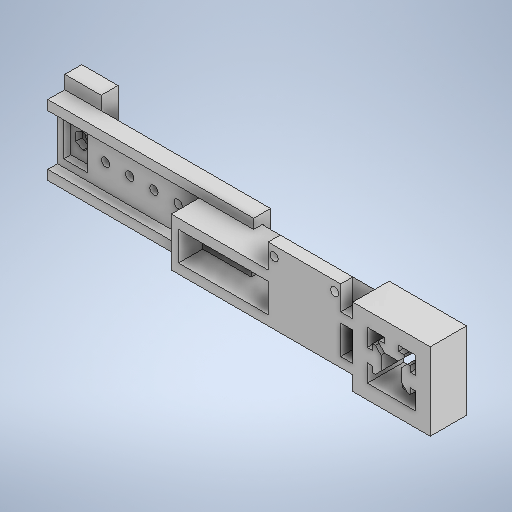
# Autodesk Inventor part: Sujetador_Camara_Modular
Saved by Autodesk Inventor 2025.3 (Build 293356030, 356C)
## iProperties
Created: 2026-06-30
Part Number: Sujetador_Camara_Modular
Material: Generic
Document SubType Name: Modeling
Designer: pablo
Density: 1 g/cm^3
Appearance: Default
Author: pablo
Autodesk Inventor part; units mm, degrees
ref_plane "YZ Plane" through (0, 0, 0) normal (1, 0, 0) x (0, 1, 0)
ref_plane "XZ Plane" through (0, 0, 0) normal (0, 1, 0) x (-1, 0, 0)
ref_plane "XY Plane" through (0, 0, 0) normal (0, 0, 1) x (1, 0, 0)
sketch "Sketch1" plane through (0, 0, 0) normal (0, 0, 1) x (1, 0, 0)
  line L0 (-2.8, -10) -> (-2.8, -7.8)
  line L1 (-2.8, -7.8) -> (-5.2, -7.8)
  line L2 (-5.2, -6.7) -> (-2.8, -4.3)
  line L3 (-7.8, -5.2) -> (-6.7, -5.2)
  line L4 (-6.7, -5.2) -> (-4.3, -2.8)
  line L5 (-2.8, -10) -> (-10, -10)
  line L6 (-7.8, -2.8) -> (-7.8, -5.2)
  line L7 (-7.8, -2.8) -> (-10, -2.8)
  line L8 (-10, -10) -> (-10, -2.8)
  line L9 (-5.2, -7.8) -> (-5.2, -6.7)
  line L10 (-4.3, -2.8) -> (-4.3, 0)
  line L11 (-4.3, 2.8) -> (-4.3, 0)
  line L12 (2.8, -10) -> (2.8, -7.8)
  line L13 (-10, -10) -> (10, -10)
  line L14 (2.8, -4.3) -> (0, -4.3)
  line L15 (5.2, -6.7) -> (2.8, -4.3)
  line L16 (6.7, -5.2) -> (4.3, -2.8)
  line L17 (2.8, -7.8) -> (5.2, -7.8)
  line L18 (2.8, -10) -> (10, -10)
  line L19 (5.2, -7.8) -> (5.2, -6.7)
  line L20 (-5.2, 6.7) -> (-2.8, 4.3)
  line L21 (-2.8, -4.3) -> (0, -4.3)
  line L22 (10, 10) -> (-10, 10)
  line L23 (2.8, 10) -> (10, 10)
  line L24 (-2.8, 7.8) -> (-5.2, 7.8)
  line L25 (-2.8, 10) -> (-2.8, 7.8)
  line L26 (2.8, 10) -> (2.8, 7.8)
  line L27 (2.8, 7.8) -> (5.2, 7.8)
  line L28 (-5.2, 7.8) -> (-5.2, 6.7)
  line L29 (5.2, 7.8) -> (5.2, 6.7)
  line L30 (-7.8, 5.2) -> (-6.7, 5.2)
  line L31 (-2.8, 4.3) -> (0, 4.3)
  line L32 (-6.7, 5.2) -> (-4.3, 2.8)
  line L33 (-7.8, 2.8) -> (-10, 2.8)
  line L34 (-7.8, 2.8) -> (-7.8, 5.2)
  line L35 (4.3, 2.8) -> (4.3, 0)
  line L36 (-10, 0) -> (10, 0) construction
  line L37 (10, -10) -> (10, 10)
  line L38 (-2.8, 10) -> (-10, 10)
  line L39 (0, -10) -> (0, 10) construction
  line L40 (-10, 10) -> (-10, 2.8)
  line L41 (7.8, 5.2) -> (6.7, 5.2)
  line L42 (2.8, 4.3) -> (0, 4.3)
  line L43 (5.2, 6.7) -> (2.8, 4.3)
  line L44 (7.8, 2.8) -> (10, 2.8)
  line L45 (6.7, 5.2) -> (4.3, 2.8)
  line L46 (7.8, 2.8) -> (7.8, 5.2)
  line L47 (10, 10) -> (10, 2.8)
  line L48 (7.8, -2.8) -> (10, -2.8)
  line L49 (7.8, -5.2) -> (6.7, -5.2)
  line L50 (7.8, -2.8) -> (7.8, -5.2)
  line L51 (10, 10) -> (10, -10) construction
  line L52 (10, -10) -> (10, -2.8)
  line L53 (4.3, -2.8) -> (4.3, 0)
  line L54 (-10, 10) -> (-10, -10)
  line L55 (16, 16) -> (-16, 16)
  line L56 (-16, 16) -> (-16, -16)
  line L57 (-16, -16) -> (16, -16)
  line L58 (16, -16) -> (16, 16)
  line L59 (16, 16) -> (-16, -16) construction
  line L60 (-16, 16) -> (16, -16) construction
  line L61 (-10, 10) -> (-16, 10)
  line L62 (-10, -10) -> (-16, -10)
  line L63 (-4.5, -16) -> (-12.5, -16)
  point P0 (0, 0)
  point P1 (0, 0)
  point P2 (0, 0)
  point P3 (-8.5, -16)
  point P4 (0, 0)
  point P5 (10, -2.8)
  dimension "d0" = 20
  dimension "d1" = 20
  dimension "d2" = 7.2
  dimension "d3" = 7.2
  dimension "d4" = 2.2
  dimension "d5" = 2.2
  dimension "d6" = 2.8
  dimension "d7" = 5.2
  dimension "d8" = 5.2
  dimension "d9" = 2.8
  dimension "d10" = 1.1
  dimension "d11" = 1.1
  dimension "d12" = 5.7
  dimension "d13" = 5.7
  dimension "d14" = 2.8
  dimension "d15" = 2.8
  dimension "d16" = 45
  dimension "d17" = 32
  dimension "d18" = 32
  constraints: 128 end point, 32 symmetric about line, 9 midpoint, 9 perpendicular, 7 point on line, 5 horizontal, 5 parallel, 2 coincident, 2 vertical, 1 horizontal alignment
  measures "d0" distance of L54.start L51.start
  measures "d1" distance of L51.start L13.end
  measures "d2" distance between parallel lines of L5 L7
  measures "d3" distance between parallel lines of L8 L0
  measures "d4" distance between parallel lines of L5 L1
  measures "d5" distance between parallel lines of L54 L6
  measures "d6" distance from line of L39.start L0
  measures "d7" distance from line of L39.start L9
  measures "d8" distance between parallel lines of L36 L3
  measures "d9" distance between parallel lines of L36 L7
  measures "d10" distance of L1.end L9.end
  measures "d11" distance of L6.end L4.start
  measures "d12" distance between parallel lines of L13 L21
  measures "d13" distance between parallel lines of L54 L10
  measures "d14" distance of L2.end L21.end
  measures "d15" distance of L10.start L10.end
  measures "d16" angle of L5 L2
  measures "d17" distance of L57.end L57.start
  measures "d18" distance between parallel lines of L55 L57
extrude "Extrusion1" add sketch "Sketch1" along normal blind 15 contours L13 L37 L22 L61 L56 L55 L58 L57 L62 L5 | L62 L56 L61 L40 L54 L8 | L54 L33 L34 L30 L32 L11 L10 L4 L3 L6 L7 | L48 L50 L49 L16 L53 L35 L45 L41 L46 L44 L37 | L22 L26 L27 L29 L43 L42 L31 L20 L28 L24 L25
sketch "Sketch2" plane through (-16, -16, 0) normal (0, -1, 0) x (1, 0, 0)
  line L0 (0, 0) -> (32, 0) projected
  line L1 (32, 0) -> (32, 15) projected
  line L2 (0, 15) -> (32, 15) projected
  line L3 (0, 0) -> (0, 15) projected
  point P0 (16, 0)
  point P1 (16, 7.5)
  point P2 (32, 7.5)
  point P3 (16, 0)
  constraints: 2 midpoint, 1 horizontal alignment, 1 vertical alignment
hole "Hole1" at (0, -16, 7.5) direction (0, 1, 0) diameter 4.2 depth 6
sketch "Sketch3" plane through (-16, -16, 0) normal (-1, 0, 0) x (0, 0, 1)
  line L0 (0, 32) -> (0, 0) projected
  line L1 (0, 0) -> (15, 0) projected
  line L2 (15, 32) -> (15, 0) projected
  line L3 (0, 32) -> (15, 32) projected
  line L4 (15, 26) -> (0, 26)
  line L5 (0, 26) -> (0, 22)
  line L6 (0, 22) -> (15, 22)
  line L7 (15, 22) -> (15, 26)
  line L8 (15, 10) -> (0, 10)
  line L9 (0, 10) -> (0, 6)
  line L10 (0, 6) -> (15, 6)
  line L11 (15, 6) -> (15, 10)
  line L12 (0, 32) -> (0, 0) projected
  point P0 (0, 16)
  point P1 (15, 8)
  point P2 (0, 16)
  point P3 (15, 24)
  point P4 (0, 16)
  dimension "d31" = 4
  dimension "d32" = 8
  dimension "d33" = 8
  dimension "d34" = 4
  constraints: 16 end point, 4 parallel, 4 point on line, 3 midpoint, 2 horizontal, 2 perpendicular, 2 other
  measures "d31" distance between parallel lines of L10 L8
  measures "d32" vertical distance of point (15, 8) point (0, 16)
  measures "d33" vertical distance of point (15, 24) point (0, 16)
  measures "d34" distance between parallel lines of L4 L6
extrude "Extrusion2" add sketch "Sketch3" along normal blind 75 contours L4 L2 L6 L0 | L8 L2 L10 L0
sketch "Sketch17" plane through (-16, 6, 0) normal (0, -1, 0) x (1, 0, 0)
  line L0 (-72, 15) -> (-72, 0)
  line L1 (0, 0) -> (-75, 0) projected
  line L2 (0, 15) -> (-75, 15) projected
  line L3 (-75, 0) -> (-75, 15) projected
  point P0 (16, 0)
  dimension "d99" = 3
  constraints: 2 end point, 2 point on line, 1 perpendicular
  measures "d99" distance between parallel lines of L3 L0
extrude "Extrusion13" add sketch "Sketch17" along normal up to surface (12 mm away)
sketch "Sketch18" plane through (0, 0, 15) normal (0, 0, 1) x (1, 0, 0)
  line L0 (-21, 20) -> (-51, 20)
  line L1 (-51, 20) -> (-51, -10)
  line L2 (-51, -10) -> (-21, -10)
  line L3 (-21, -10) -> (-21, 20)
  line L4 (-16, -10) -> (-16, -16) projected
  point P0 (0, 0)
  point P1 (-36, -10)
  dimension "d102" = 5
  dimension "d103" = 30
  dimension "d104" = 30
  constraints: 8 end point, 2 parallel, 1 horizontal, 1 horizontal alignment, 1 midpoint, 1 perpendicular
  measures "d102" distance between parallel lines of L4 L3
  measures "d103" distance of L2.end L0.start
  measures "d104" distance of L1.end L2.end
extrude "Extrusion14" add sketch "Sketch18" against normal blind 5
sketch "Sketch19" plane through (-16, -6, 15) normal (0, 1, 0) x (1, 0, 0)
  line L0 (-72, 15) -> (-72, 0) projected
  line L1 (0, 15) -> (-72, 15) projected
  line L2 (-72, 15) -> (-52, 15)
  line L3 (-52, 15) -> (-52, 10)
  line L4 (-52, 10) -> (-72, 10)
  line L5 (-72, 10) -> (-72, 15)
  point P0 (16, 15)
  dimension "d107" = 5
  dimension "d108" = 20
  constraints: 8 end point, 2 parallel, 1 horizontal, 1 perpendicular
  measures "d107" distance of L2.end L3.end
  measures "d108" distance of L3.end L4.end
extrude "Extrusion15" add sketch "Sketch19" along normal up to surface (12 mm away)
sketch "Sketch20" plane through (-88, -6, 5) normal (0, 0, 1) x (1, 0, 0)
  line L0 (20, 0) -> (0, 0) projected
  line L1 (0, 0) -> (0, 12) projected
  line L2 (14.85, 2.7091) -> (12, 4.3546)
  line L3 (12, 4.3546) -> (12, 7.6454)
  line L4 (12, 7.6454) -> (14.85, 9.2909)
  line L5 (14.85, 9.2909) -> (17.7, 7.6454)
  line L6 (17.7, 7.6454) -> (17.7, 4.3546)
  line L7 (17.7, 4.3546) -> (14.85, 2.7091)
  line L8 (7.7, 4.3546) -> (4.85, 2.7091)
  line L9 (4.85, 2.7091) -> (2, 4.3546)
  line L10 (2, 4.3546) -> (2, 7.6454)
  line L11 (2, 7.6454) -> (4.85, 9.2909)
  line L12 (4.85, 9.2909) -> (7.7, 7.6454)
  line L13 (7.7, 7.6454) -> (7.7, 4.3546)
  point P0 (88, 6)
  point P1 (14.85, 6)
  point P2 (0, 6)
  point P3 (4.85, 6)
  dimension "d111" = 5.7
  dimension "d112" = 10
  dimension "d113" = 2
  constraints: 24 end point, 2 horizontal alignment, 2 vertical, 1 midpoint, 1 parallel, 26 other
  measures "d111" distance between parallel lines of L4 L7
  measures "d112" distance of point (14.85, 6) point (4.85, 6)
  measures "d113" distance between parallel lines of L1 L10
extrude "Extrusion16" cut sketch "Sketch20" against normal blind 2.6
sketch "Sketch21" plane through (-88, -6, 2.4) normal (0, 0, 1) x (1, 0, 0)
  line L0 (4.85, 9.2909) -> (7.7, 7.6454) projected
  line L1 (2, 7.6454) -> (4.85, 9.2909) projected
  line L2 (2, 4.3546) -> (2, 7.6454) projected
  line L3 (4.85, 2.7091) -> (2, 4.3546) projected
  line L4 (7.7, 4.3546) -> (4.85, 2.7091) projected
  line L5 (7.7, 7.6454) -> (7.7, 4.3546) projected
  line L6 (17.7, 7.6454) -> (17.7, 4.3546) projected
  line L7 (14.85, 9.2909) -> (17.7, 7.6454) projected
  line L8 (12, 7.6454) -> (14.85, 9.2909) projected
  line L9 (12, 4.3546) -> (12, 7.6454) projected
  line L10 (14.85, 2.7091) -> (12, 4.3546) projected
  line L11 (17.7, 4.3546) -> (14.85, 2.7091) projected
  line L12 (12, 4.3546) -> (12, 7.6454) projected
  line L13 (7.7, 7.6454) -> (7.7, 4.3546) projected
  point P0 (88, 6)
  point P1 (4.85, 6)
  point P2 (14.85, 6)
  point P3 (12, 6)
  point P4 (7.7, 6)
  constraints: 2 horizontal alignment, 2 midpoint, 2 vertical alignment
hole "Hole5" at (-73.15, 0, 2.4) at (-83.15, 0, 2.4) direction (0, 0, -1) diameter 3.4 depth 2.4
sketch "Sketch22" plane through (0, 0, 0) normal (0, 0, -1) x (-1, 0, 0)
  circle A0 centre (73.15, 0) radius 1.7 projected
  circle A1 centre (83.15, 0) radius 1.7 projected
  line L0 (68, -6) -> (68, 6) projected
  line L1 (91, 10) -> (68, 10)
  line L2 (16, 10) -> (91, 10) projected
  line L3 (68, -10) -> (68, 10)
  line L4 (16, -10) -> (91, -10) projected
  line L5 (68, -10) -> (91, -10)
  line L6 (16, -6) -> (68, -6) projected
  line L7 (68, -6) -> (68, 6)
  line L8 (91, 10) -> (91, -10) projected
  line L9 (91, 10) -> (91, 6)
  line L10 (68, -10) -> (138, -10)
  line L11 (138, -10) -> (138, 10)
  line L12 (138, 10) -> (91, 10)
  line L13 (138, 10) -> (138, -10)
  point P0 (0, 0)
  dimension "d123" = 70
  dimension "d192" = 10
  constraints: 18 end point, 4 collinear, 4 point on line, 1 vertical
  measures "d123" distance of L3.start L10.end
  measures "d192" distance of A0.centre A1.centre
extrude "Extrusion17" add sketch "Sketch22" along normal blind 3 separate body
sketch "Sketch23" plane through (-138, 10, 0) normal (0, 1, 0) x (1, 0, 0)
  line L0 (0, 0) -> (70, 0) projected
  line L1 (70, 0) -> (70, 3) projected
  line L2 (0, 3) -> (70, 3) projected
  line L3 (0, 0) -> (0, 3) projected
  point P0 (138, 0)
extrude "Extrusion18" add sketch "Sketch23" along normal blind 4.5 bodies 2
sketch "Sketch24" plane through (-138, -10, 0) normal (0, -1, 0) x (1, 0, 0)
  line L0 (70, 0) -> (0, 0) projected
  line L1 (0, 0) -> (0, -3) projected
  line L2 (70, -3) -> (0, -3) projected
  line L3 (70, 0) -> (70, -3) projected
  point P0 (138, 0)
extrude "Extrusion19" add sketch "Sketch24" along normal blind 4.5 bodies 2
sketch "Sketch25" plane through (0, 0, 0) normal (0, 0, 1) x (1, 0, 0)
  line L0 (-138, 14.5) -> (-138, -14.5) projected
  line L1 (-138, 10.5) -> (-68, 10.5)
  line L2 (-138, -10.5) -> (-68, -10.5)
  line L3 (-68, -14.5) -> (-68, 14.5) projected
  line L4 (-138, 14.5) -> (-68, 14.5) projected
  line L5 (-68, -14.5) -> (-138, -14.5) projected
  point P0 (0, 0)
  point P1 (-93, 10.5)
  dimension "d131" = 4
  dimension "d132" = 4
  constraints: 4 end point, 4 point on line, 2 horizontal
  measures "d131" distance between parallel lines of L1 L4
  measures "d132" distance between parallel lines of L5 L2
extrude "Extrusion20" add sketch "Sketch25" along normal blind 4 contours L4 L3 L1 L0 | L2 L3 L5 L0 bodies 2
sketch "Sketch26" plane through (0, 0, -3) normal (0, 0, -1) x (-1, 0, 0)
  circle A0 centre (73.15, 0) radius 1.7 projected
  line L0 (138, -14.5) -> (68, -14.5) projected
  circle A1 centre (83.15, 0) radius 1.7 projected
  point P0 (0, 0)
  point P1 (93.15, 0)
  point P2 (103.15, 0)
  point P3 (103.15, 0)
  point P4 (113.15, 0)
  point P5 (123.15, 0)
  point P6 (123.15, 0)
  point P7 (133.15, 0)
  dimension "d195" = 20
  dimension "d202" = 10
  constraints: 4 coincident, 2 horizontal, 7 other
  measures "d195" distance of point (73.15, 0) point (93.15, 0)
  measures "d202" distance of point (123.15, 0) point (133.15, 0)
hole "Hole6" at (-93.15, 0, -3) at (-103.15, 0, -3) at (-113.15, 0, -3) at (-123.15, 0, -3) at (-133.15, 0, -3) direction (0, 0, 1) diameter 3.4 depth 3 bodies 2
sketch "Sketch27" plane through (-138, -14.5, -3) normal (-1, 0, 0) x (0, 0, 1)
  line L0 (0, 29) -> (7, 29) projected
  line L1 (0, 29) -> (0, 0) projected
  line L2 (0, 0) -> (7, 0) projected
  line L3 (7, 4) -> (7, 0) projected
  line L4 (3, 4) -> (7, 4) projected
  line L5 (3, 25) -> (3, 4) projected
  line L6 (3, 25) -> (7, 25) projected
  line L7 (7, 29) -> (7, 25) projected
  point P0 (3, 14.5)
extrude "Extrusion21" add sketch "Sketch27" along normal blind 15 bodies 2
sketch "Sketch28" plane through (0, 0, -3) normal (0, 0, -1) x (-1, 0, 0)
  line L0 (153, 14.5) -> (153, -14.5) projected
  line L1 (153, -20) -> (138, -20)
  line L2 (138, -20) -> (138, 20)
  line L3 (138, 20) -> (153, 20)
  line L4 (153, 20) -> (153, -20)
  point P0 (0, 0)
  point P1 (153, 0)
  point P2 (153, 0)
  dimension "d151" = 15
  dimension "d152" = 40
  constraints: 8 end point, 3 midpoint, 2 parallel, 1 coincident, 1 horizontal, 1 perpendicular
  measures "d151" distance of L2.end L3.end
  measures "d152" distance of L3.end L1.start
extrude "Extrusion22" add sketch "Sketch28" along normal blind 7 bodies 2
sketch "Sketch29" plane through (0, 0, -10) normal (0, 0, -1) x (-1, 0, 0)
  line L0 (138, 20) -> (138, -20) projected
  line L1 (138, -20) -> (153, -20) projected
  line L2 (153, -20) -> (153, 20) projected
  line L3 (153, 20) -> (138, 20) projected
  line L4 (140.25, -18.25) -> (150.75, -18.25)
  line L5 (150.75, -18.25) -> (150.75, 18.25)
  line L6 (150.75, 18.25) -> (140.25, 18.25)
  line L7 (140.25, 18.25) -> (140.25, -18.25)
  line L8 (140.25, -18.25) -> (150.75, 18.25) construction
  line L9 (150.75, -18.25) -> (140.25, 18.25) construction
  line L10 (150.75, -11) -> (153, -11)
  line L11 (150.75, 11) -> (153, 11)
  line L12 (153, -20) -> (153, 20) projected
  point P0 (0, 0)
  point P1 (145.5, 0)
  point P2 (153, 0)
  point P3 (145.5, 20)
  point P4 (153, 0)
  dimension "d155" = 10.5
  dimension "d156" = 36.5
  dimension "d157" = 22
  dimension "d158" = 11
  constraints: 16 end point, 5 midpoint, 4 point on line, 3 perpendicular, 2 parallel, 1 horizontal, 1 horizontal alignment, 1 vertical alignment
  measures "d155" distance of L5.end L6.end
  measures "d156" distance of L4.end L5.end
  measures "d157" distance between parallel lines of L10 L11
  measures "d158" distance from line of point (153, 0) L11
extrude "Extrusion23" cut sketch "Sketch29" against normal blind 3 contours L2 L10 L5 L11 | L5 L4 L7 L6 bodies 2
sketch "Sketch30" plane through (0, 0, -7) normal (0, 0, -1) x (-1, 0, 0)
  line L0 (140.25, 18.25) -> (150.75, 18.25) projected
  line L1 (140.25, -18.25) -> (140.25, 18.25) projected
  point P0 (0, 0)
  point P1 (145.5, 0)
  point P2 (140.25, 0)
  point P3 (145.5, 18.25)
  constraints: 2 midpoint, 1 horizontal alignment, 1 vertical alignment
hole "Hole7" at (-145.5, 0, -7) direction (0, 0, 1) diameter 3.4 depth 11 bodies 2
sketch "Sketch33" plane through (0, 0, 15) normal (0, 0, 1) x (1, 0, 0)
  line L0 (-51, 20) -> (-51, 10) projected
  line L1 (-21, 20) -> (-51, 20) projected
  line L2 (-21, 10) -> (-21, 20) projected
  point P0 (0, 0)
  point P1 (-48.5, 16)
  point P2 (-23.5, 16)
  dimension "d175" = 2.5
  dimension "d176" = 2.5
  dimension "d177" = 4
  constraints: 1 horizontal alignment
  measures "d175" distance from line of L2 point (-23.5, 16)
  measures "d176" distance from line of L0 point (-48.5, 16)
  measures "d177" distance from line of L1 point (-23.5, 16)
hole "Hole8" at (-48.5, 16, 15) at (-23.5, 16, 15) direction (0, 0, -1) diameter 3.4 depth 5 bodies 1
sketch "Sketch36" plane through (0, 0, 0) normal (0, 0, 1) x (1, 0, 0)
  circle A0 centre (-145.5, 0) radius 1.7 projected
  line L0 (-148.45, 1.7032) -> (-145.5, 3.4064)
  line L1 (-145.5, 3.4064) -> (-142.55, 1.7032)
  line L2 (-142.55, 1.7032) -> (-142.55, -1.7032)
  line L3 (-142.55, -1.7032) -> (-145.5, -3.4064)
  line L4 (-145.5, -3.4064) -> (-148.45, -1.7032)
  line L5 (-148.45, -1.7032) -> (-148.45, 1.7032)
  point P0 (0, 0)
  dimension "d207" = 5.9
  constraints: 12 end point, 1 coincident, 1 vertical, 13 other
  measures "d207" distance between parallel lines of L1 L4
extrude "Extrusion28" cut sketch "Sketch36" against normal blind 5.6 bodies 2
sketch "Sketch37" plane through (0, 0, 0) normal (0, 0, 1) x (1, 0, 0)
  circle A0 centre (-145.5, 0) radius 1.7 projected
  line L0 (-140.5, -7.5) -> (-150.5, -7.5)
  line L1 (-150.5, -7.5) -> (-150.5, 7.5)
  line L2 (-150.5, 7.5) -> (-140.5, 7.5)
  line L3 (-140.5, 7.5) -> (-140.5, -7.5)
  circle A1 centre (-145.5, 0) radius 1.7 projected
  line L4 (-140.5, -7.5) -> (-150.5, 7.5) construction
  line L5 (-150.5, -7.5) -> (-140.5, 7.5) construction
  point P0 (0, 0)
  dimension "d210" = 10
  dimension "d211" = 15
  constraints: 12 end point, 2 midpoint, 2 parallel, 1 horizontal, 1 perpendicular
  measures "d210" distance of L1.end L2.end
  measures "d211" distance of L0.end L1.end
extrude "Extrusion29" cut sketch "Sketch37" against normal blind 3 bodies 2
equation "\"d1\" = d0"
equation "\"d2\" = d3"
equation "\"d5\" = d4"
equation "\"d8\" = d7"
equation "\"d11\" = d10"
equation "\"d13\" = d12"
equation "\"d18\" = d17"
